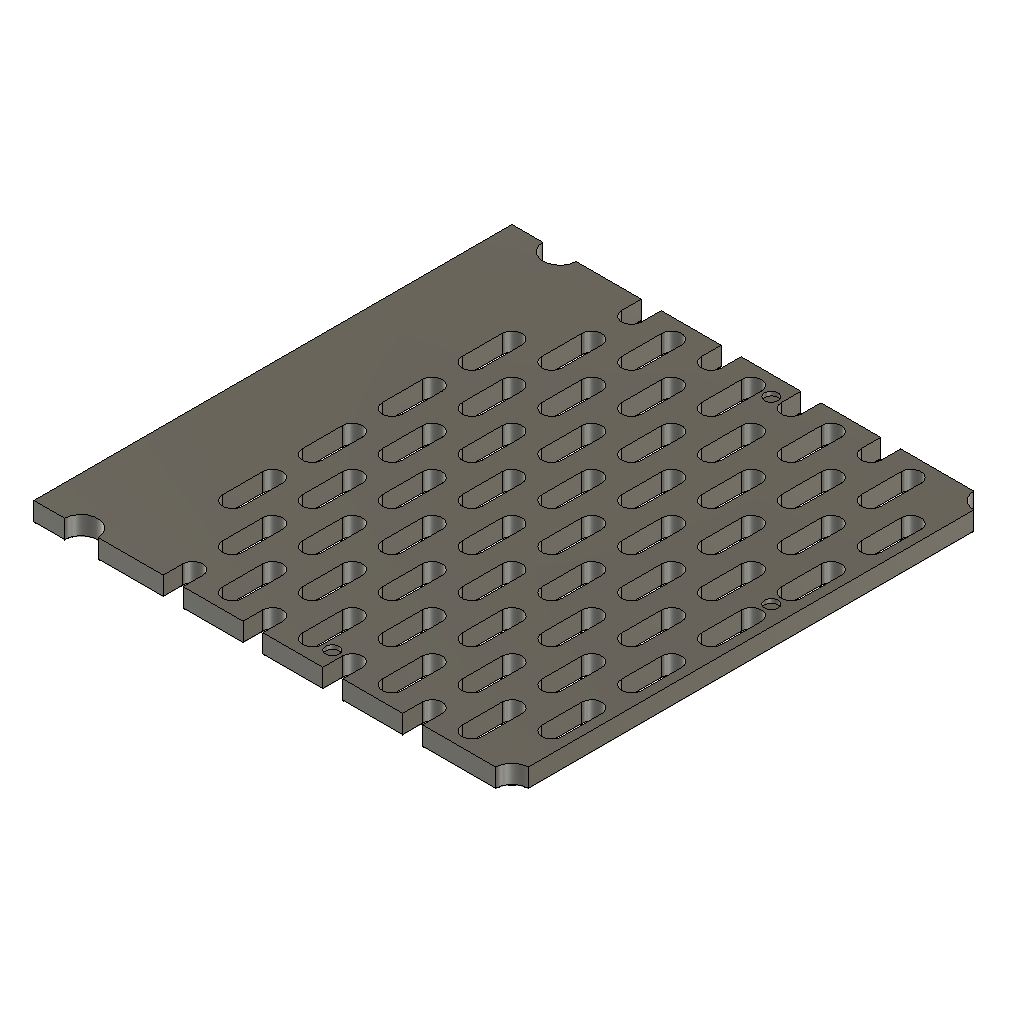
panel-left-edge-v02 (Autodesk Fusion 360 design; units mm, degrees)
part number: 2026-10-27-14-47-32-446
part number: 2026-10-27-14-47-32-883
Autodesk Fusion 360 part; units mm, degrees
sketch "01 Panel blank sketch" plane through (0, 0, 0) normal (0, 0, 1) x (1, 0, 0) in component "Panel left-edge"
  line L0 (0.1, 0.1) -> (119.9, 0.1)
  line L1 (119.9, 0.1) -> (119.9, 119.9)
  line L2 (119.9, 119.9) -> (0.1, 119.9)
  line L3 (0.1, 119.9) -> (0.1, 0.1)
  dimension "d31" = 0.1
  dimension "d32" = 0.1
  dimension "d33" = 119.8
  dimension "d34" = 119.8
  constraint horizontal L0
  constraint vertical L1
  constraint horizontal L2
  constraint vertical L3
  measures "d31" horizontal distance of origin L0.start
  measures "d32" vertical distance of origin L0.start
  measures "d33" horizontal distance of L0.start L0.end
  measures "d34" vertical distance of L0.end L1.end
extrude "01 Panel blank" add sketch "01 Panel blank sketch" along normal blind 5 in component "Panel left-edge"
sketch "03 A main constrained seed" plane through (0, 0, 0) normal (0, 0, 1) x (1, 0, 0) in component "Panel left-edge"
  line L0 (47.5, 5) -> (47.5, 15)
  arc A0 (47.5, 15) -> (42.5, 15) centre (45, 15) ccw
  line L1 (42.5, 15) -> (42.5, 5)
  arc A1 (42.5, 5) -> (47.5, 5) centre (45, 5) ccw
  line L2 (45, 5) -> (45, 15) construction
  line L3 (45, 5) -> (55, 5) construction
  dimension "d37" = 5
  dimension "d38" = 10
  dimension "d39" = 90
  dimension "d40" = 10
  dimension "d41" = 45
  dimension "d42" = 5
  constraint tangent L0 A0
  constraint tangent A0 L1
  constraint tangent L1 A1
  constraint tangent L0 A1
  constraint parallel L0 L1
  constraint horizontal L3
  measures "d37" diameter of A0
  measures "d38" distance of A1.centre A0.centre
  measures "d39" angle of L2 L3
  measures "d40" horizontal distance of A1.centre L3.end
  measures "d41" horizontal distance of origin A1.centre
  measures "d42" vertical distance of origin A1.centre
extrude "03 A main through cut" cut sketch "03 A main constrained seed" along normal blind 5 in component "Panel left-edge"
pattern_linear "03 A main lattice" count 4 spacing 20 along (1, 0, 0) count 6 spacing 20 along (0, 1, 0) of "03 A main through cut" in component "Panel left-edge"
sketch "04 A end strip constrained seed" plane through (0, 0, 0) normal (0, 0, 1) x (1, 0, 0) in component "Panel left-edge"
  line L0 (27.5, 25) -> (27.5, 35)
  arc A0 (27.5, 35) -> (22.5, 35) centre (25, 35) ccw
  line L1 (22.5, 35) -> (22.5, 25)
  arc A1 (22.5, 25) -> (27.5, 25) centre (25, 25) ccw
  line L2 (25, 25) -> (25, 35) construction
  line L3 (25, 25) -> (35, 25) construction
  dimension "d49" = 5
  dimension "d50" = 10
  dimension "d51" = 90
  dimension "d52" = 10
  dimension "d53" = 25
  dimension "d54" = 25
  constraint tangent L0 A0
  constraint tangent A0 L1
  constraint tangent L1 A1
  constraint tangent L0 A1
  constraint parallel L0 L1
  constraint horizontal L3
  measures "d49" diameter of A0
  measures "d50" distance of A1.centre A0.centre
  measures "d51" angle of L2 L3
  measures "d52" horizontal distance of A1.centre L3.end
  measures "d53" horizontal distance of origin A1.centre
  measures "d54" vertical distance of origin A1.centre
extrude "04 A end strip through cut" cut sketch "04 A end strip constrained seed" along normal blind 5 in component "Panel left-edge"
pattern_linear "04 A end strip lattice" count 1 spacing 20 along (1, 0, 0) count 4 spacing 20 along (0, 1, 0) of "04 A end strip through cut" in component "Panel left-edge"
sketch "05 B main constrained seed" plane through (0, 0, 0) normal (0, 0, 1) x (1, 0, 0) in component "Panel left-edge"
  line L0 (37.5, -5) -> (37.5, 5)
  arc A0 (37.5, 5) -> (32.5, 5) centre (35, 5) ccw
  line L1 (32.5, 5) -> (32.5, -5)
  arc A1 (32.5, -5) -> (37.5, -5) centre (35, -5) ccw
  line L2 (35, -5) -> (35, 5) construction
  line L3 (35, -5) -> (45, -5) construction
  dimension "d61" = 5
  dimension "d62" = 10
  dimension "d63" = 90
  dimension "d64" = 10
  dimension "d65" = 35
  dimension "d66" = 5
  constraint tangent L0 A0
  constraint tangent A0 L1
  constraint tangent L1 A1
  constraint tangent L0 A1
  constraint parallel L0 L1
  constraint horizontal L3
  measures "d61" diameter of A0
  measures "d62" distance of A1.centre A0.centre
  measures "d63" angle of L2 L3
  measures "d64" horizontal distance of A1.centre L3.end
  measures "d65" horizontal distance of origin A1.centre
  measures "d66" vertical distance of origin A1.centre
extrude "05 B main through cut" cut sketch "05 B main constrained seed" along normal blind 5 in component "Panel left-edge"
pattern_linear "05 B main lattice" count 4 spacing 20 along (1, 0, 0) count 7 spacing 20 along (0, 1, 0) of "05 B main through cut" in component "Panel left-edge"
sketch "06 B end strip constrained seed" plane through (0, 0, 0) normal (0, 0, 1) x (1, 0, 0) in component "Panel left-edge"
  line L0 (117.5, 15) -> (117.5, 25)
  arc A0 (117.5, 25) -> (112.5, 25) centre (115, 25) ccw
  line L1 (112.5, 25) -> (112.5, 15)
  arc A1 (112.5, 15) -> (117.5, 15) centre (115, 15) ccw
  line L2 (115, 15) -> (115, 25) construction
  line L3 (115, 15) -> (125, 15) construction
  dimension "d73" = 5
  dimension "d74" = 10
  dimension "d75" = 90
  dimension "d76" = 10
  dimension "d77" = 115
  dimension "d78" = 15
  constraint tangent L0 A0
  constraint tangent A0 L1
  constraint tangent L1 A1
  constraint tangent L0 A1
  constraint parallel L0 L1
  constraint horizontal L3
  measures "d73" diameter of A0
  measures "d74" distance of A1.centre A0.centre
  measures "d75" angle of L2 L3
  measures "d76" horizontal distance of A1.centre L3.end
  measures "d77" horizontal distance of origin A1.centre
  measures "d78" vertical distance of origin A1.centre
extrude "06 B end strip through cut" cut sketch "06 B end strip constrained seed" along normal blind 5 in component "Panel left-edge"
pattern_linear "06 B end strip lattice" count 1 spacing 20 along (1, 0, 0) count 5 spacing 20 along (0, 1, 0) of "06 B end strip through cut" in component "Panel left-edge"
sketch "07 Shared node clearance sketch" plane through (0, 0, 0) normal (0, 0, 1) x (1, 0, 0) in component "Panel left-edge"
  circle A0 centre (12, 0) radius 4.2
  dimension "d85" = 12
  dimension "d86" = 8.4
  constraint horizontal origin A0.centre
  measures "d85" horizontal distance of origin A0.centre
  measures "d86" diameter of A0
extrude "07 Shared node clearance" cut sketch "07 Shared node clearance sketch" along normal blind 5 in component "Panel left-edge"
sketch "07 Shared node clearance sketch (1)" plane through (0, 0, 0) normal (0, 0, 1) x (1, 0, 0) in component "Panel left-edge"
  circle A0 centre (12, 120) radius 4.2
  dimension "d89" = 12
  dimension "d90" = 120
  dimension "d91" = 8.4
  measures "d89" horizontal distance of origin A0.centre
  measures "d90" vertical distance of origin A0.centre
  measures "d91" diameter of A0
extrude "07 Shared node clearance (1)" cut sketch "07 Shared node clearance sketch (1)" along normal blind 5 in component "Panel left-edge"
sketch "07 Shared node clearance sketch (2)" plane through (0, 0, 0) normal (0, 0, 1) x (1, 0, 0) in component "Panel left-edge"
  circle A0 centre (120, 0) radius 4.2
  dimension "d94" = 120
  dimension "d95" = 8.4
  constraint horizontal origin A0.centre
  measures "d94" horizontal distance of origin A0.centre
  measures "d95" diameter of A0
extrude "07 Shared node clearance (2)" cut sketch "07 Shared node clearance sketch (2)" along normal blind 5 in component "Panel left-edge"
sketch "07 Shared node clearance sketch (3)" plane through (0, 0, 0) normal (0, 0, 1) x (1, 0, 0) in component "Panel left-edge"
  circle A0 centre (120, 120) radius 4.2
  dimension "d98" = 120
  dimension "d99" = 120
  dimension "d100" = 8.4
  measures "d98" horizontal distance of origin A0.centre
  measures "d99" vertical distance of origin A0.centre
  measures "d100" diameter of A0
extrude "07 Shared node clearance (3)" cut sketch "07 Shared node clearance sketch (3)" along normal blind 5 in component "Panel left-edge"
fillet "08 Rounded slot entrances and face edges" radius 0.4 2 faces at (7.5667, 61.6667, 0) (7.5667, 61.6667, 0) in component "Panel left-edge"
ref_plane "WorkPlane1" through (0, 0, 5) normal (0, 0, 1) x (1, 0, 0) in component "Panel left-edge"
sketch "09 Blind rear key socket sketch" plane through (0, 0, 5) normal (0, 0, 1) x (1, 0, 0) in component "Panel left-edge"
  circle A0 centre (115, 70) radius 1.7
  dimension "d107" = 115
  dimension "d108" = 70
  dimension "d109" = 3.4
  measures "d107" horizontal distance of origin A0.centre
  measures "d108" vertical distance of origin A0.centre
  measures "d109" diameter of A0
extrude "09 Blind rear key socket" cut sketch "09 Blind rear key socket sketch" against normal blind 1 in component "Panel left-edge"
ref_plane "WorkPlane2" through (0, 0, 5) normal (0, 0, 1) x (1, 0, 0) in component "Panel left-edge"
sketch "09 Blind rear key socket sketch (1)" plane through (0, 0, 5) normal (0, 0, 1) x (1, 0, 0) in component "Panel left-edge"
  circle A0 centre (70, 5) radius 1.7
  dimension "d114" = 70
  dimension "d115" = 5
  dimension "d116" = 3.4
  measures "d114" horizontal distance of origin A0.centre
  measures "d115" vertical distance of origin A0.centre
  measures "d116" diameter of A0
extrude "09 Blind rear key socket (1)" cut sketch "09 Blind rear key socket sketch (1)" against normal blind 1 in component "Panel left-edge"
ref_plane "WorkPlane3" through (0, 0, 5) normal (0, 0, 1) x (1, 0, 0) in component "Panel left-edge"
sketch "09 Blind rear key socket sketch (2)" plane through (0, 0, 5) normal (0, 0, 1) x (1, 0, 0) in component "Panel left-edge"
  circle A0 centre (70, 115) radius 1.7
  dimension "d121" = 70
  dimension "d122" = 115
  dimension "d123" = 3.4
  measures "d121" horizontal distance of origin A0.centre
  measures "d122" vertical distance of origin A0.centre
  measures "d123" diameter of A0
extrude "09 Blind rear key socket (2)" cut sketch "09 Blind rear key socket sketch (2)" against normal blind 1 in component "Panel left-edge"
component "Panel left-edge" placed x (1, 0, 0) y (0, 1, 0) z (0, 0, 1) at (0, 0, 0)
equation "columns = 6" comment "Even integer 4..14; each cell is 20 mm"
equation "rows = 6" comment "Even integer 4..14"
equation "pitch = 20 mm" comment "Keep for dense SKADIS compatible lattice"
equation "panelWidth = columns * pitch" comment "Nominal module pitch X"
equation "panelHeight = rows * pitch" comment "Nominal module pitch Y"
equation "seamGap = 0.2 mm" comment "Physical envelope shrinks around fixed lattice"
equation "boardThickness = 5 mm" comment "Fit-test with real hooks"
equation "slotWidth = 5 mm" comment "Minimum throat width"
equation "slotHeight = 15 mm" comment "Minimum throat height"
equation "entryRadius = 0.4 mm" comment "Front slot and perimeter edge rounding"
equation "cornerRadius = 6 mm" comment "Plan-view panel corner rounding"
equation "hookClearance = 10 mm" comment "PROVISIONAL: board rear to front of extrusion"
equation "frameZ = boardThickness + hookClearance" comment "Front extrusion datum"
equation "mountInset = 12 mm" comment "Exterior node inset from outside module edge"
equation "mountBore = 8.4 mm" comment "Clearance around 8 mm metal shoulder"
equation "capDiameter = 18 mm" comment "Visible decorative mounting disk"
equation "capThickness = 2 mm" comment "Metal clamping cap / washer"
equation "seatThickness = 2 mm" comment "Printed rear bearing washer"
equation "screwDiameter = 5 mm" comment "Nominal M5 reference, threads omitted"
equation "screwClearance = 5.5 mm" comment "Cap and spacer bore"
equation "keyWidth = 4 mm" comment "Registration key corridor width"
equation "keyThickness = 2 mm" comment "Rear removable key body"
equation "keyPegDiameter = 3 mm" comment "Rear locating peg"
equation "keySocketDiameter = 3.4 mm" comment "0.2 mm radial starting fit"
equation "keyPegHeight = 0.8 mm" comment "Peg penetration"
equation "keySocketDepth = 1 mm" comment "Blind locating pocket"
equation "panelLeft = 1" comment "0 internal / 1 finished; full cell border and inset mounting"
equation "panelRight = 0" comment "0 internal / 1 finished; full cell border and inset mounting"
equation "panelBottom = 0" comment "0 internal / 1 finished; full cell border and inset mounting"
equation "panelTop = 0" comment "0 internal / 1 finished; full cell border and inset mounting"
equation "d31 = abs(( 0 mm ) + seamGap / 2)"
equation "d32 = abs(( 0 mm ) + seamGap / 2)"
equation "d33 = panelWidth - seamGap"
equation "d34 = panelHeight - seamGap"
equation "d35 = boardThickness"
equation "d37 = slotWidth"
equation "d38 = slotHeight - slotWidth"
equation "d40 = pitch / 2"
equation "d41 = abs(( 0 mm ) + pitch / 4 + pitch * ( panelLeft + 1 ))"
equation "d42 = abs(( ( 0 mm ) + pitch / 2 + pitch * panelBottom ) - ( slotHeight - slotWidth ) / 2)"
equation "d43 = boardThickness"
equation "d45 = columns - panelLeft - panelRight - 1"
equation "d46 = rows - panelBottom - panelTop"
equation "d47 = pitch"
equation "d48 = pitch"
equation "d49 = slotWidth"
equation "d50 = slotHeight - slotWidth"
equation "d52 = pitch / 2"
equation "d53 = abs(( 0 mm ) + pitch / 4 + pitch * panelLeft)"
equation "d54 = abs(( ( 0 mm ) + 3 * pitch / 2 + pitch * panelBottom ) - ( slotHeight - slotWidth ) / 2)"
equation "d55 = boardThickness"
equation "d58 = rows - panelBottom - panelTop - 2"
equation "d59 = pitch"
equation "d60 = pitch"
equation "d61 = slotWidth"
equation "d62 = slotHeight - slotWidth"
equation "d64 = pitch / 2"
equation "d65 = abs(( 0 mm ) + 3 * pitch / 4 + pitch * panelLeft)"
equation "d66 = abs(( ( 0 mm ) + pitch * panelBottom ) - ( slotHeight - slotWidth ) / 2)"
equation "d67 = boardThickness"
equation "d69 = columns - panelLeft - panelRight - 1"
equation "d70 = rows + 1 - panelBottom - panelTop"
equation "d71 = pitch"
equation "d72 = pitch"
equation "d73 = slotWidth"
equation "d74 = slotHeight - slotWidth"
equation "d76 = pitch / 2"
equation "d77 = abs(( 0 mm ) + panelWidth - pitch / 4 - pitch * panelRight)"
equation "d78 = abs(( ( 0 mm ) + pitch + pitch * panelBottom ) - ( slotHeight - slotWidth ) / 2)"
equation "d79 = boardThickness"
equation "d82 = rows - 1 - panelBottom - panelTop"
equation "d83 = pitch"
equation "d84 = pitch"
equation "d85 = abs(( 0 mm ) + mountInset * panelLeft)"
equation "d86 = mountBore"
equation "d87 = boardThickness"
equation "d89 = abs(( 0 mm ) + mountInset * panelLeft)"
equation "d90 = abs(( 0 mm ) + panelHeight - mountInset * panelTop)"
equation "d91 = mountBore"
equation "d92 = boardThickness"
equation "d94 = abs(( 0 mm ) + panelWidth - mountInset * panelRight)"
equation "d95 = mountBore"
equation "d96 = boardThickness"
equation "d98 = abs(( 0 mm ) + panelWidth - mountInset * panelRight)"
equation "d99 = abs(( 0 mm ) + panelHeight - mountInset * panelTop)"
equation "d100 = mountBore"
equation "d101 = boardThickness"
equation "d104 = entryRadius"
equation "d105 = boardThickness"
equation "d107 = abs(( 0 mm ) + panelWidth - pitch / 4)"
equation "d108 = abs(( 0 mm ) + panelHeight / 2 + pitch / 2)"
equation "d109 = keySocketDiameter"
equation "d110 = -keySocketDepth"
equation "d112 = boardThickness"
equation "d114 = abs(( 0 mm ) + panelWidth / 2 + pitch / 2)"
equation "d115 = abs(( 0 mm ) + pitch / 4)"
equation "d116 = keySocketDiameter"
equation "d117 = -keySocketDepth"
equation "d119 = boardThickness"
equation "d121 = abs(( 0 mm ) + panelWidth / 2 + pitch / 2)"
equation "d122 = abs(( 0 mm ) + panelHeight - pitch / 4)"
equation "d123 = keySocketDiameter"
equation "d124 = -keySocketDepth"
named bodies: "Panel left-edge"
